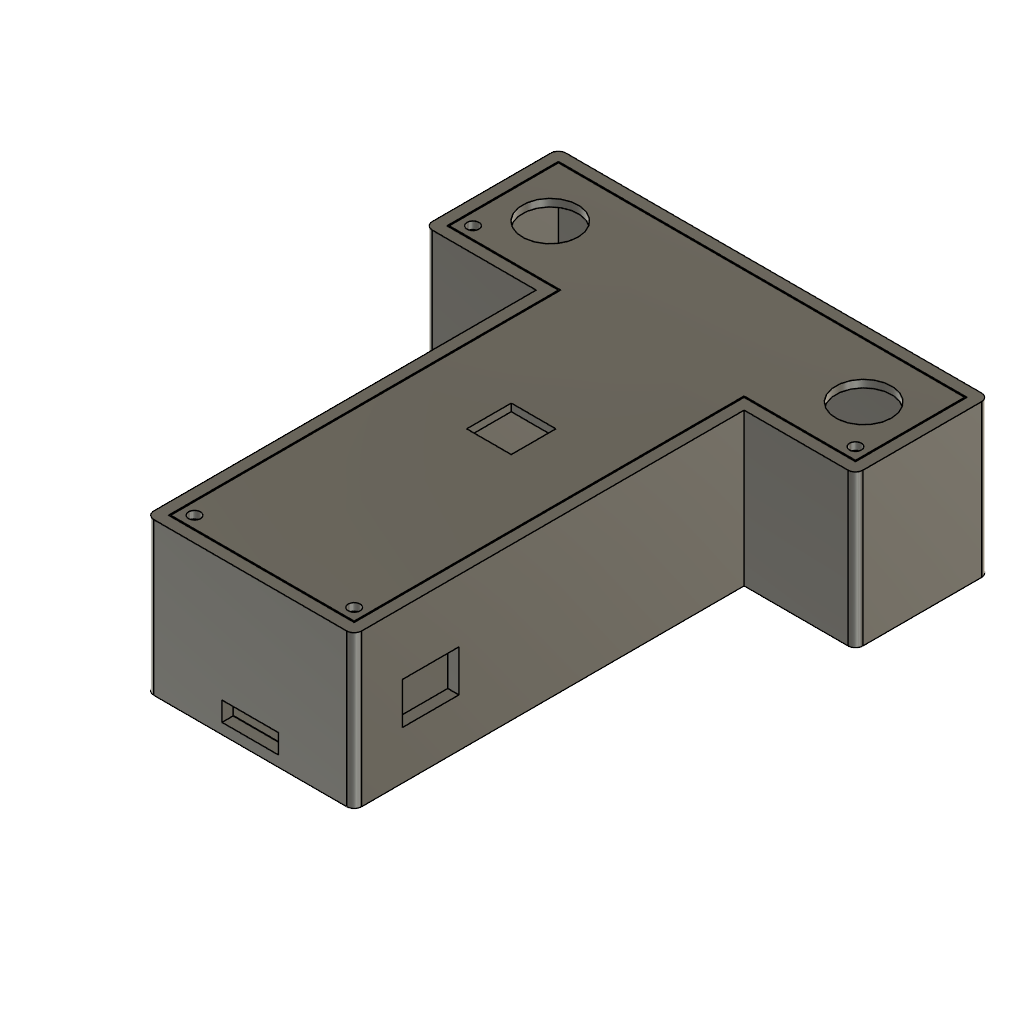
SpectrumAnalyzerEnclosure (Autodesk Fusion 360 design; units mm, degrees)
part number: 2026-05-27-17-20-15-398
Autodesk Fusion 360 part; units mm, degrees
sketch "Sketch1" plane through (0, 0, 0) normal (0, 0, 1) x (1, 0, 0)
  line L0 (0, 0) -> (50, 0)
  line L1 (50, 0) -> (50, 105)
  line L2 (0, 105) -> (0, 0)
  line L3 (80, 135) -> (-30, 135)
  line L4 (-30, 135) -> (-30, 105)
  line L5 (80, 105) -> (80, 135)
  line L6 (80, 135) -> (-30, 105) construction
  line L7 (-30, 135) -> (80, 105) construction
  line L8 (-30, 105) -> (0, 105)
  line L9 (50, 105) -> (80, 105)
  dimension "d3" = 50
  dimension "d4" = 105
  dimension "d7" = 110
  dimension "d8" = 30
  dimension "d10" = 30
  dimension "d11" = 50
  constraint horizontal L0
  constraint vertical L1
  constraint vertical L2
  constraint coincident L0.start L2.end
  constraint horizontal L3
  constraint perpendicular L3 L4
  constraint parallel L3 L8
  constraint parallel L4 L5
  constraint collinear L8 L9
  measures "d3" distance of L0.start L0.end
  measures "d4" distance of L0.start L2.start
  measures "d7" distance of L4.end L5.start
  measures "d8" distance of L3.end L4.end
  measures "d10" distance of L1.end L5.start
  measures "d11" distance of L0.start L0.end
extrude "Extrude1" add sketch "Sketch1" along normal blind 38 makes body 1
shell "Shell1" thickness 3 outward yes removed faces 1 at (16.6667, 70, 38) on bodies 1
sketch "Sketch2" plane through (0, -3, 0) normal (0, -1, 0) x (1, 0, 0)
  line L0 (-3, -3) -> (53, -3)
  line L1 (53, -3) -> (53, 38)
  line L2 (53, 38) -> (-3, 38)
  line L3 (-3, 38) -> (-3, -3)
  line L4 (32.6, 5.1) -> (17.4, 5.1)
  line L5 (17.4, 5.1) -> (17.4, -0.1)
  line L6 (17.4, -0.1) -> (32.6, -0.1)
  line L7 (32.6, -0.1) -> (32.6, 5.1)
  line L8 (32.6, 5.1) -> (17.4, -0.1) construction
  line L9 (17.4, 5.1) -> (32.6, -0.1) construction
  point P0 (25, 2.5)
  dimension "d15" = 15.2
  dimension "d16" = 5.2
  constraint horizontal L4
  constraint perpendicular L4 L5
  constraint parallel L4 L6
  constraint parallel L5 L7
  constraint coincident L8 P0
  constraint coincident L9 P0
  measures "d15" distance of L5.end L6.end
  measures "d16" distance of L4.end L5.end
extrude "Extrude2" cut sketch "Sketch2" against normal blind 3 contours L4 L5 L6 L7 bodies 1
sketch "Sketch3" plane through (53, 0, 0) normal (1, 0, 0) x (0, 1, 0)
  line L0 (-3, -3) -> (102, -3)
  line L1 (102, -3) -> (102, 38)
  line L2 (102, 38) -> (-3, 38)
  line L3 (-3, 38) -> (-3, -3)
  line L4 (10, 10) -> (25.2, 10)
  line L5 (25.2, 10) -> (25.2, 21.2)
  line L6 (25.2, 21.2) -> (10, 21.2)
  line L7 (10, 21.2) -> (10, 10)
  dimension "d21" = 15.2
  dimension "d22" = 11.2
  constraint horizontal L4
  constraint vertical L5
  constraint horizontal L6
  constraint vertical L7
  measures "d21" distance of L4.start L4.end
  measures "d22" distance of L4.start L6.end
extrude "Extrude3" cut sketch "Sketch3" against normal blind 3 contours L4 L5 L6 L7 bodies 1
sketch "Sketch4" plane through (0, 0, 0) normal (0, 0, 1) x (-1, 0, 0)
  line L0 (-50, -105) -> (-80, -105)
  line L1 (-80, -105) -> (-80, -135)
  line L2 (-80, -135) -> (30, -135)
  line L3 (30, -135) -> (30, -105)
  line L4 (30, -105) -> (0, -105)
  line L5 (0, -105) -> (0, 0)
  line L6 (0, 0) -> (-17.4, 0)
  line L7 (-17.4, 0) -> (-32.6, 0)
  line L8 (-32.6, 0) -> (-50, 0)
  line L9 (-50, 0) -> (-50, -105)
  circle A0 centre (-3.5, -3.5) radius 3.5
  circle A1 centre (-3.5, -3.5) radius 1.25
  circle A2 centre (-46.5, -3.5) radius 3.5
  circle A3 centre (-46.5, -3.5) radius 1.25
  circle A4 centre (-76.5, -108.5) radius 3.5
  circle A5 centre (-76.5, -108.5) radius 1.25
  circle A6 centre (26.5, -108.5) radius 3.5
  circle A7 centre (26.5, -108.5) radius 1.25
  dimension "d27" = 7
  dimension "d28" = 2.5
  dimension "d33" = 7
  dimension "d34" = 2.5
  dimension "d39" = 7
  dimension "d40" = 2.5
  dimension "d43" = 7
  dimension "d44" = 2.5
  constraint concentric A2 A3
  constraint concentric A6 A7
  measures "d27" diameter of A0
  measures "d28" diameter of A1
  measures "d33" diameter of A2
  measures "d34" diameter of A3
  measures "d39" diameter of A4
  measures "d40" diameter of A5
  measures "d43" diameter of A6
  measures "d44" diameter of A7
extrude "Extrude4" add sketch "Sketch4" along normal blind 36 contours L5 L6 A0 | A0 bodies 1
extrude "Extrude5" add sketch "Sketch4" along normal blind 36 contours L8 L9 A2 | A2 bodies 1
extrude "Extrude6" add sketch "Sketch4" along normal blind 36 contours L0 L1 A4 | A4 | L3 L4 A6 | A6 bodies 1
sketch "Sketch7" plane through (0, 0, 38) normal (0, 0, 1) x (-1, 0, 0)
  line L0 (-50, -105) -> (-50, 0)
  line L1 (-50, 0) -> (0, 0)
  line L2 (0, 0) -> (0, -105)
  line L3 (0, -105) -> (30, -105)
  line L4 (30, -105) -> (30, -135)
  line L5 (30, -135) -> (-80, -135)
  line L6 (-80, -135) -> (-80, -105)
  line L7 (-80, -105) -> (-50, -105)
  line L8 (-53, -102) -> (-83, -102)
  line L9 (-83, -102) -> (-83, -138)
  line L10 (-83, -138) -> (33, -138)
  line L11 (33, -138) -> (33, -102)
  line L12 (33, -102) -> (3, -102)
  line L13 (3, -102) -> (3, 3)
  line L14 (3, 3) -> (-53, 3)
  line L15 (-53, 3) -> (-53, -102)
  line L16 (29.7, -105.3) -> (29.7, -134.7)
  line L17 (29.7, -134.7) -> (-79.7, -134.7)
  line L18 (-79.7, -134.7) -> (-79.7, -105.3)
  line L19 (-79.7, -105.3) -> (-49.7, -105.3)
  line L20 (-49.7, -105.3) -> (-49.7, -0.3)
  line L21 (-49.7, -0.3) -> (-0.3, -0.3)
  line L22 (-0.3, -0.3) -> (-0.3, -105.3)
  line L23 (-0.3, -105.3) -> (29.7, -105.3)
  dimension "d47" = 0.3
extrude "Extrude7" add sketch "Sketch7" against normal blind 2 separate body contours L16 L17 L18 L19 L20 L21 L22 L23 makes body 2
sketch "Sketch8" plane through (0, 0, 38) normal (0, 0, 1) x (-1, 0, 0)
  line L0 (-0.3, -105.3) -> (-0.3, -0.3)
  line L1 (-0.3, -0.3) -> (-49.7, -0.3)
  line L2 (-49.7, -0.3) -> (-49.7, -105.3)
  line L3 (-49.7, -105.3) -> (-79.7, -105.3)
  line L4 (-79.7, -105.3) -> (-79.7, -134.7)
  line L5 (-79.7, -134.7) -> (29.7, -134.7)
  line L6 (29.7, -134.7) -> (29.7, -105.3)
  line L7 (29.7, -105.3) -> (-0.3, -105.3)
  circle A0 centre (-3.5, -3.5) radius 1.6
  circle A1 centre (-46.5, -3.5) radius 1.6
  circle A2 centre (-76.5, -108.5) radius 1.6
  circle A3 centre (26.5, -108.5) radius 1.6
  line L8 (-32, -60.3) -> (-20, -60.3)
  line L9 (-20, -60.3) -> (-20, -72.3)
  line L10 (-20, -72.3) -> (-32, -72.3)
  line L11 (-32, -72.3) -> (-32, -60.3)
  line L12 (-32, -60.3) -> (-20, -72.3) construction
  line L13 (-20, -60.3) -> (-32, -72.3) construction
  circle A4 centre (17.2, -120) radius 7.5
  circle A5 centre (-67.2, -120) radius 7.5
  point P0 (-26, -66.3)
  dimension "d50" = 3.2
  dimension "d51" = 3.2
  dimension "d52" = 3.2
  dimension "d53" = 3.2
  dimension "d58" = 12
  dimension "d59" = 12
  dimension "d66" = 15
  dimension "d67" = 15
  constraint horizontal L8
  constraint perpendicular L8 L9
  constraint parallel L8 L10
  constraint parallel L9 L11
  constraint coincident L12 P0
  constraint coincident L13 P0
  measures "d50" diameter of A0
  measures "d51" diameter of A1
  measures "d52" diameter of A2
  measures "d53" diameter of A3
  measures "d58" distance of L9.end L10.end
  measures "d59" distance of L8.end L9.end
  measures "d66" diameter of A4
  measures "d67" diameter of A5
extrude "Extrude8" cut sketch "Sketch8" against normal blind 2 contours A0 | A1 | A2 | A3 bodies 2
extrude "Extrude9" cut sketch "Sketch8" against normal blind 2 contours L8 L9 L10 L11 | A4 | A5 bodies 2
fillet "Fillet1" radius 2 1 edges at (-33, 102, 17.5) on bodies 1
fillet "Fillet2" radius 2 1 edges at (-33, 138, 17.5) on bodies 1
fillet "Fillet3" radius 2 1 edges at (-3, -3, 17.5) on bodies 1
fillet "Fillet4" radius 2 1 edges at (53, -3, 17.5) on bodies 1
fillet "Fillet5" radius 2 1 edges at (83, 102, 17.5) on bodies 1
fillet "Fillet6" radius 2 1 edges at (83, 138, 17.5) on bodies 1
equation "Wall_Thickness = 3 mm"
equation "Tolerance = 0.2 mm"
equation "d14 = Wall_Thickness"
equation "d15 = 15 mm + Tolerance"
equation "d16 = 5 mm + Tolerance"
equation "d21 = 15 mm + Tolerance"
equation "d22 = 11 mm + Tolerance"
